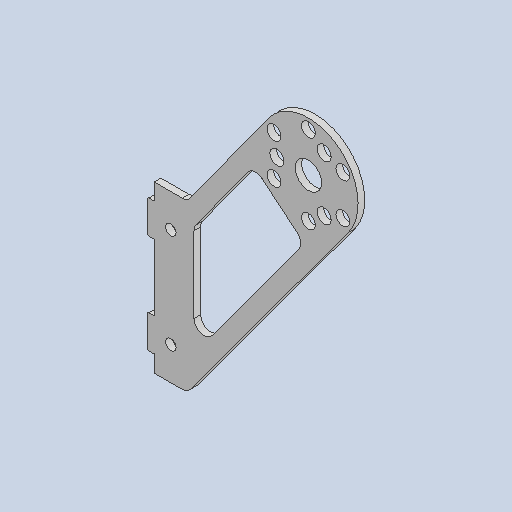
# Autodesk Inventor part: plate_prAltNew
Saved by Autodesk Inventor 2025.3 (Build 293356000, 356)
## iProperties
Created: 2026-10-19
Part Number: plate_prAltNew
Material: 一般
Document SubType Name: Modeling
Designer: yunto
Density: 1 g/cm^3
Appearance: 既定
Author: yunto
Autodesk Inventor part; units mm, degrees
ref_plane "YZ Plane" through (0, 0, 0) normal (1, 0, 0) x (0, 1, 0)
ref_plane "XZ Plane" through (0, 0, 0) normal (0, 1, 0) x (-1, 0, 0)
ref_plane "XY Plane" through (0, 0, 0) normal (0, 0, 1) x (1, 0, 0)
sketch "スケッチ1" plane through (0, 0, 0) normal (0, 0, 1) x (1, 0, 0)
  line L0 (-5, 25) -> (5, 25)
  line L1 (5, -25) -> (-5, -25)
  line L2 (-5, -25) -> (-5, 25)
  line L3 (-5, 0) -> (0, 0) construction
  line L4 (0, 15) -> (0, -15) construction
  circle A0 centre (0, 15) radius 1.6
  circle A1 centre (0, -15) radius 1.6
  line L5 (-7.1, 20) -> (-5, 20)
  line L6 (-5, 20) -> (-5, 10)
  line L7 (-5, 10) -> (-7.1, 10)
  line L8 (-7.1, 10) -> (-7.1, 20)
  line L9 (-7.1, -10) -> (-5, -10)
  line L10 (-5, -10) -> (-5, -20)
  line L11 (-5, -20) -> (-7.1, -20)
  line L12 (-7.1, -20) -> (-7.1, -10)
  line L13 (5, 25) -> (29.3686, 58.7763)
  line L14 (5, -25) -> (53.6175, 41.1136)
  line L15 (0, 0) -> (41.5331, 50) construction
  circle A2 centre (41.5331, 50) radius 15
  circle A3 centre (41.5331, 62) radius 2.1
  circle A4 centre (31.1408, 56) radius 2.1
  circle A5 centre (31.1408, 44) radius 2.1
  circle A6 centre (41.5331, 38) radius 2.1
  circle A7 centre (51.9254, 44) radius 2.1
  circle A8 centre (51.9254, 56) radius 2.1
  line L16 (41.5331, 50) -> (41.5331, 62) construction
  circle A9 centre (46.2831, 58.2272) radius 2.15
  line L17 (41.5331, 50) -> (46.2831, 58.2272) construction
  circle A10 centre (32.0331, 50) radius 2.15
  circle A11 centre (46.2831, 41.7728) radius 2.15
  circle A12 centre (41.5331, 50) radius 4
  line L18 (7, 19.2264) -> (25.0261, 44.2117)
  line L19 (25.0261, 44.2117) -> (40.3369, 31.4936)
  line L20 (40.3369, 31.4936) -> (7, -13.8404)
  line L21 (7, -13.8404) -> (7, 19.2264)
  point P0 (-7.1, 15)
  point P1 (-7.1, -15)
  dimension "d2" = 10
  dimension "d3" = 3.2
  dimension "d4" = 5
  dimension "d5" = 30
  dimension "d6" = 10
  dimension "d7" = 15
  dimension "d8" = 15
  dimension "d9" = 50
  dimension "d11" = 2.1
  dimension "d21" = 30
  dimension "d22" = 12
  dimension "d23" = 4.2
  dimension "d24" = 360
  dimension "d25" = 4.3
  dimension "d26" = 9.5
  dimension "d27" = 30
  dimension "d28" = 360
  dimension "d29" = 8
  dimension "d31" = 50
  dimension "d32" = 65
  dimension "d35" = 12
  dimension "d36" = 5
  dimension "d37" = 5
  dimension "d38" = 15
  constraints: 44 end point, 13 centre point, 8 parallel, 6 coincident, 4 horizontal, 4 midpoint, 3 equal length, 3 perpendicular, 2 point on circle, 2 tangent, 2 vertical, 1 collinear, 1 equal radius, 1 point on line, 20 other
  measures "d2" distance of L0.start L13.start
  measures "d3" diameter of A0
  measures "d4" distance of L3.start L15.start
  measures "d5" distance of L4.start L4.end
  measures "d6" distance of L7.end L5.start
  measures "d7" vertical distance of L3.start point (-7.1, 15)
  measures "d8" vertical distance of point (-7.1, -15) L3.start
  measures "d9" distance of L2.start L0.start
  measures "d11" distance of L11.start L11.end
  measures "d21" diameter of A2
  measures "d22" distance of point (41.533, 50) L16.end
  measures "d23" diameter of A3
  measures "d25" diameter of A9
  measures "d26" distance of L16.start L17.end
  measures "d27" angle of L17 L16
  measures "d29" diameter of A12
  measures "d31" vertical distance of L15.end point (0, 0)
  measures "d32" distance of L15.start L15.end
  measures "d35" distance from line of L6.start L21
  measures "d36" distance between parallel lines of L13 L18
  measures "d37" distance between parallel lines of L14 L20
  measures "d38" distance from line of L15.end L19
extrude "押し出し1" add sketch "スケッチ1" along normal blind 2
fillet "フィレット1" radius 3 6 edges at (5, -25, 1) (5, 25, 1) (7, 19.2264, 1) (7, -13.8404, 1) (40.3369, 31.4936, 1) (25.0261, 44.2117, 1)
fillet "フィレット2" radius 0.5 4 edges at (-7.1, -20, 1) (-7.1, -10, 1) (-7.1, 10, 1) (-7.1, 20, 1)
equation "\"d8\" = d7"
equation "\"d31\" = pitchOffset"
equation "\"d32\" = pitchLength"
equation "\"d37\" = d36"
equation "\"pitchLength\" = 65"
equation "\"pitchOffset\" = 50"
equation "\"pRSdeg\" = 30deg"
equation "\"handDeg\" = 60deg"
